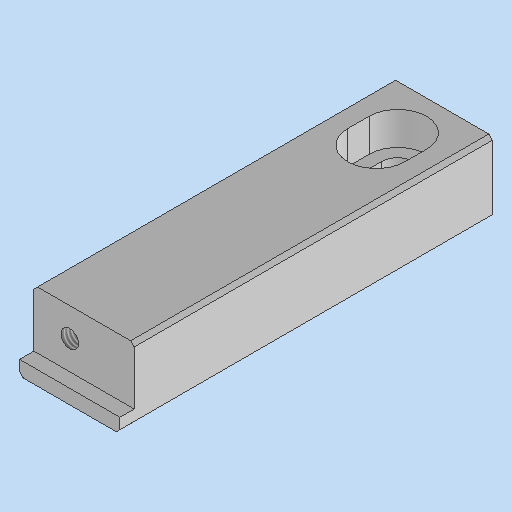
# Autodesk Inventor part: MM0948AN160_G01_161
Saved by Autodesk Inventor 2023.3 (Build 273359000, 359)
## iProperties
Created: 2023-07-12
Part Number: MM0948AN160_G01_161
Material: 1.2210 115CrV3
Description: =<RBPARTNOTITLE2>
Document SubType Name: Modeling
Designer: RIC7AN
Mass: 50.5996 g
Surface Area: 29.4517 cm^2
Volume: 6.48713 cm^3
Density: 7.8 g/cm^3
Appearance: silber AnP
Vendor: --
RBPARTMADEOF: 10 x 52 x 14 (FM)
RBDRAWINGMISSINGSPEC: --
AnP_Kategorie: 1
RBPARTNOTITLE2: Anfertigungsteil
RBSURFACE: chemically nickel-coated
RBPARTNOTITLE1: manufactured part
RBSURFACE2: chem. vernickelt
AnP_Material: =<Material>
RBMATERIAL: =<Material>
RBMATNO: =<Part Number>
RBPARTNO: SIEHE MNR
MaxAbmaße: 10 x 52 x 14 (FM)
Author: RIC7AN
Keywords: =<RBPARTMADEOF>
Comments: =<RBSURFACE2>
Revision Number: 01
Autodesk Inventor part; units mm, degrees
ref_plane "YZ Plane" through (0, 0, 0) normal (1, 0, 0) x (0, 1, 0)
ref_plane "XZ Plane" through (0, 0, 0) normal (0, 1, 0) x (-1, 0, 0)
ref_plane "XY Plane" through (0, 0, 0) normal (0, 0, 1) x (1, 0, 0)
sketch "Skizze1" plane through (0, 0, 0) normal (0, 0, 1) x (1, 0, 0)
  line L0 (-7, 52) -> (7, 52)
  line L1 (7, 52) -> (7, 0)
  line L2 (7, 0) -> (-7, 0)
  line L3 (-7, 0) -> (-7, 52)
  line L4 (0, 62.4) -> (0, -10.4) projected
  line L5 (-9.8, 0) -> (9.8, 0) projected
  point P0 (0, 0)
  dimension "d0" = 14
  dimension "d1" = 52
  constraints: 8 end point, 2 parallel, 1 collinear, 1 horizontal, 1 perpendicular, 1 other
  measures "d0" distance of L0.start L0.end
  measures "d1" distance of L0.end L1.end
extrude "Extrusion1" add sketch "Skizze1" along normal blind 10
sketch "Skizze2" plane through (-7, 0, 0) normal (0, -1, 0) x (1, 0, 0)
  line L0 (14, 0) -> (14, 10) projected
  line L1 (0, 10) -> (14, 10) projected
  line L2 (0, 0) -> (0, 10) projected
  line L3 (0, 10) -> (14, 10)
  line L4 (14, 10) -> (14, 2)
  line L5 (14, 2) -> (0, 2)
  line L6 (0, 2) -> (0, 10)
  point P0 (0, 2)
  dimension "d32" = 8
  constraints: 8 end point, 2 parallel, 1 horizontal, 1 perpendicular, 1 point on line
  measures "d32" distance between parallel lines of L1 L5
extrude "Extrusion2" cut sketch "Skizze2" against normal blind 2
sketch "Skizze3" plane through (-7, 2, 0) normal (0, -1, 0) x (1, 0, 0)
  line L0 (0, 2) -> (0, 10) projected
  line L1 (0, 10) -> (14, 10) projected
  point P0 (5, 6)
  dimension "d8" = 5
  dimension "d33" = 4
  measures "d8" distance from line of point (5, 6) L0
  measures "d33" distance from line of L1 point (5, 6)
hole "Bohrung1" at (-2, 2, 6) direction (0, 1, 0) diameter 2.459 depth 8.8 tip angle 118 thread size "M3x0.5" designation "M3" class "6H" standard "ISO Metric profile"
sketch "Skizze4" plane through (0, 0, 10) normal (0, 0, 1) x (1, 0, 0)
  line L0 (0, 62.4) -> (0, -10.4) projected
  line L1 (-7, 0) -> (7, 0) projected
  point P0 (0, 0)
  point P1 (0, 44.3)
  dimension "d16" = 44.3
  constraints: 1 point on line
  measures "d16" distance from line of L1 point (0, 44.3)
hole "Bohrung2" at (0, 44.3, 10) direction (0, 0, -1) diameter 4.5 end through all counterbore diameter 8 counterbore depth 4.6 clearance for "Inbusschraube ISO 4762  versenkt" size "M4" standard "ISO"
sketch "Skizze5" plane through (0, 0, 10) normal (0, 0, 1) x (1, 0, 0)
  circle A0 centre (0, 44.3) radius 2.25 projected
  line L0 (0, 45.8) -> (0, 42.8) construction
  line L1 (-2.25, 45.8) -> (-2.25, 42.8)
  line L2 (2.25, 42.8) -> (2.25, 45.8)
  arc A1 (2.25, 45.8) -> (-2.25, 45.8) centre (0, 45.8) ccw
  arc A2 (-2.25, 42.8) -> (2.25, 42.8) centre (0, 42.8) ccw
  point P0 (0, 0)
  point P1 (2.25, 44.3)
  point P2 (-2.25, 44.3)
  dimension "d24" = 3
  constraints: 8 end point, 5 tangent, 4 point on circle, 2 centre point, 1 coincident, 1 midpoint, 1 parallel, 1 vertical
  measures "d24" distance of L0.start L0.end
extrude "Extrusion3" cut sketch "Skizze5" against normal through all contours L2 A2 L1 A0 | A0 L1 A1 L2
sketch "Skizze6" plane through (0, 0, 10) normal (0, 0, 1) x (1, 0, 0)
  circle A0 centre (0, 44.3) radius 4 projected
  line L0 (0, 45.8) -> (0, 42.8) construction
  line L1 (-4, 45.8) -> (-4, 42.8)
  line L2 (4, 42.8) -> (4, 45.8)
  arc A1 (4, 45.8) -> (-4, 45.8) centre (0, 45.8) ccw
  arc A2 (-4, 42.8) -> (4, 42.8) centre (0, 42.8) ccw
  arc A3 (2.25, 45.8) -> (-2.25, 45.8) centre (0, 45.8) ccw projected
  arc A4 (-2.25, 42.8) -> (2.25, 42.8) centre (0, 42.8) ccw projected
  point P0 (0, 0)
  point P1 (4, 44.3)
  point P2 (-4, 44.3)
  constraints: 8 end point, 5 tangent, 4 point on circle, 2 centre point, 2 coincident, 1 midpoint, 1 parallel, 1 vertical
extrude "Extrusion4" cut sketch "Skizze6" against normal up to surface (4.6 mm away) contours L2 A2 L1 A0 | A0 L1 A1 L2
chamfer "Fase1" distance 0.5 angle 45 4 edges at (-7, 27, 10) (7, 27, 10) (7, 26, 0) (-7, 26, 0)
